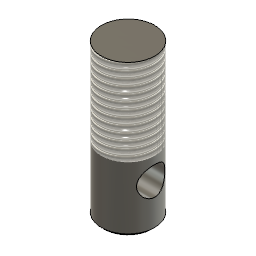
screw1 (Autodesk Fusion 360 design; units mm, degrees)
part number: 2026-08-20-14-31-36-616
Autodesk Fusion 360 part; units mm, degrees
sketch "Sketch1" plane through (0, 0, 0) normal (0, 1, 0) x (1, 0, 0)
  circle A0 centre (0, 0) radius 10
  dimension "d1" = 20
  constraint coincident A0.centre origin
  measures "d1" diameter of A0
extrude "Extrude1" add sketch "Sketch1" along normal blind 56
sketch "Sketch2" plane through (0, 0, 0) normal (1, 0, 0) x (0, 0, -1)
  circle A0 centre (0, 16) radius 5.25
  dimension "d4" = 10.5
  dimension "d5" = 16
  measures "d4" diameter of A0
  measures "d5" distance of origin A0.centre
extrude "Extrude2" cut sketch "Sketch2" along normal mid plane 40
thread "Thread1" "ISO Metric profile 20.0 M20x2.5 M20x2.5 6g" major diameter 19.7905 minor diameter 16.938 pitch 2.5 angle 60 resizes the face on face at (7.7578, 24.0417, 6.31) from (0, 24, 0) to (0, 56, 0)
chamfer "Chamfer1" distance 1 angle 45 1 edges at (-9.2256, 0, 3.5783) tangent chain off
